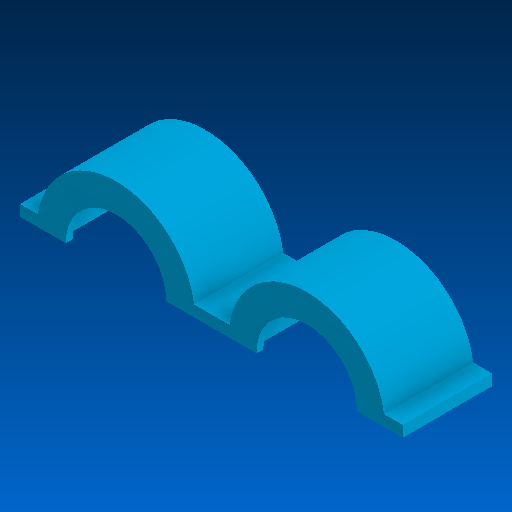
# Autodesk Inventor part: Bilge Pump Holder
Saved by Autodesk Inventor 2019 (Build 230136000, 136)
## iProperties
Created: 2018-10-23
Part Number: Bilge Pump Holder
Material: Generic
Document SubType Name: Modeling
Designer: -----
Density: 1 g/cm^3
Appearance: Sky Blue Medium
Mass: 43.4068 g
Surface Area: 140.518 cm^2
Volume: 43.4068 cm^3
Author: -----
Autodesk Inventor part; units mm, degrees
ref_plane "YZ Plane" through (0, 0, 0) normal (1, 0, 0) x (0, 1, 0)
ref_plane "XZ Plane" through (0, 0, 0) normal (0, 1, 0) x (-1, 0, 0)
ref_plane "XY Plane" through (0, 0, 0) normal (0, 0, 1) x (1, 0, 0)
sketch "Sketch1" plane through (0, 0, 0) normal (0, 1, 0) x (-1, 0, 0)
  line L0 (-0.1069, 50.4998) -> (-0.1069, 25.4998)
  arc A0 (-0.1069, -25.4998) -> (-0.1069, 25.4998) centre (0, 0) ccw
  line L1 (-0.1069, -25.4998) -> (-0.1069, -50.4998)
  line L2 (-0.1069, 50.4998) -> (4.8931, 50.4998)
  line L3 (4.8931, 50.4998) -> (4.8931, 34.6563)
  line L4 (4.8931, -34.6563) -> (4.8931, -50.4998)
  line L5 (4.8931, -50.4998) -> (-0.1069, -50.4998)
  arc A1 (4.8931, -34.6563) -> (4.8931, 34.6563) centre (0, 0) ccw
  circle A2 centre (0, 0) radius 25.5 projected
  dimension "d0" = 51
  dimension "d2" = 25
  dimension "d3" = 5
  dimension "d4" = 25
  dimension "d12" = 35
  constraints: 12 end point, 4 point on circle, 3 point on line, 2 centre point, 2 coincident, 2 vertical, 1 collinear, 1 horizontal, 1 perpendicular
  measures "d0" diameter of A0
  measures "d2" distance of L0.start L0.end
  measures "d3" distance of L0.start L2.end
  measures "d4" distance of L1.start L1.end
  measures "d12" radius of A1
extrude "Extrusion1" add sketch "Sketch1" along normal blind 34 contours L2 L3 A1 L4 L5 L1 A0 L0
sketch "Sketch2" plane through (0, 34, 0) normal (0, 1, 0) x (1, 0, 0)
  line L0 (0.1069, -50.4998) -> (0.1069, -25.4998) projected
  arc A0 (0.1069, 25.4998) -> (0.1069, -25.4998) centre (0, 0) ccw projected
  line L1 (0.1069, 25.4998) -> (0.1069, 50.4998) projected
  line L2 (0.1069, 50.4998) -> (-4.8931, 50.4998) projected
  line L3 (-4.8931, 50.4998) -> (-4.8931, 34.6563) projected
  arc A1 (-4.8931, 34.6563) -> (-4.8931, -34.6563) centre (0, 0) ccw projected
  line L4 (-4.8931, -34.6563) -> (-4.8931, -50.4998) projected
  line L5 (-4.8931, -50.4998) -> (0.1069, -50.4998) projected
  circle A2 centre (0, 0) radius 22.5
  line L6 (0.1069, -22.4997) -> (0.1069, -25.4998)
  line L7 (0.1069, 22.4997) -> (0.1069, 25.4998)
  dimension "d7" = 45
  constraints: 4 end point, 2 point on circle, 1 centre point, 1 coincident, 1 collinear, 1 point on line, 1 vertical
  measures "d7" diameter of A2
extrude "Extrusion2" add sketch "Sketch2" along normal blind 3 contours L5 L4 A1 L3 L2 L1 A0 L0 | A0 L7 A2 L6
sketch "Sketch8" plane through (0, 0, 0) normal (0, -1, 0) x (1, 0, 0)
  line L0 (0.1069, 50.4998) -> (0.1069, 25.4998) projected
  line L1 (-4.8931, 50.4998) -> (0.1069, 50.4998) projected
  line L2 (-4.8931, 34.6563) -> (-4.8931, 50.4998) projected
  arc A0 (-4.8931, 34.6563) -> (-4.8931, -34.6563) centre (0, 0) ccw projected
  line L3 (-4.8931, -50.4998) -> (-4.8931, -34.6563) projected
  line L4 (0.1069, -50.4998) -> (-4.8931, -50.4998) projected
  line L5 (0.1069, -25.4998) -> (0.1069, -50.4998) projected
  arc A1 (0.1069, 25.4998) -> (0.1069, -25.4998) centre (0, 0) ccw projected
  arc A2 (0.1069, 22.4997) -> (0.1069, -22.4997) centre (0, 0) ccw projected
  line L6 (0.1069, -22.4997) -> (0.1069, -25.4998) projected
  line L7 (0.1069, 25.4998) -> (0.1069, 22.4997) projected
extrude "Extrusion7" add sketch "Sketch8" along normal blind 3
sketch "Sketch12" plane through (0, 37, 0) normal (0, 1, 0) x (1, 0, 0)
  line L0 (0.1069, -50.4998) -> (0.1069, -22.4997) projected
  arc A0 (0.1069, 22.4997) -> (0.1069, -22.4997) centre (0, 0) ccw projected
  line L1 (0.1069, 22.4997) -> (0.1069, 50.4998) projected
  line L2 (0.1069, 50.4998) -> (-4.8931, 50.4998) projected
  line L3 (-4.8931, 50.4998) -> (-4.8931, 34.6563) projected
  arc A1 (-4.8931, 34.6563) -> (-4.8931, -34.6563) centre (0, 0) ccw projected
  line L4 (-4.8931, -34.6563) -> (-4.8931, -50.4998) projected
  line L5 (-4.8931, -50.4998) -> (0.1069, -50.4998) projected
  arc A2 (0.1069, 25.4998) -> (0.1069, -25.4998) centre (0, 0) ccw projected
  arc A3 (0.1069, 25.4998) -> (0.1069, -25.4998) centre (0, 0) ccw projected
  line L6 (0.1069, 50.4998) -> (0.1069, 85.4998)
  line L7 (0.1069, 50.4998) -> (-4.8931, 50.4998) projected
  arc A4 (-4.8931, 120.4998) -> (0.1069, 50.1444) centre (0.1069, 85.4998) ccw
  arc A5 (0.1069, 110.9998) -> (0.1069, 59.9998) centre (0.1069, 85.4998) ccw
  line L8 (0.1069, 85.4998) -> (0.1069, 120.8551)
  line L9 (0.1069, 110.9998) -> (0.1069, 135.9998)
  line L10 (0.1069, 135.9998) -> (-4.8931, 135.9998)
  line L11 (-4.8931, 135.9998) -> (-4.8931, 120.4998)
  dimension "d64" = 35
  dimension "d65" = 22.5
  dimension "d66" = 25.5
  dimension "d67" = 35
  dimension "d68" = 51
  dimension "d69" = 15.8435
  dimension "d70" = 25
  dimension "d71" = 5
  constraints: 10 end point, 5 point on circle, 4 point on line, 2 centre point, 2 coincident, 2 vertical, 1 horizontal, 1 perpendicular
  measures "d64" radius of A1
  measures "d65" radius of A0
  measures "d66" radius of A2
  measures "d67" distance of L1.end L6.end
  measures "d68" diameter of A5
  measures "d69" distance of L2.end L3.end
  measures "d70" distance of L9.start L9.end
  measures "d71" distance of L9.end L10.end
extrude "Extrusion8" add sketch "Sketch12" against normal blind 40 contours L2 A4 L11 L10 L9 L8 A5 L6
sketch "Sketch13" plane through (0, 37, 0) normal (0, 1, 0) x (1, 0, 0)
  line L0 (0.1069, -50.4998) -> (0.1069, -22.4997) projected
  arc A0 (0.1069, 22.4997) -> (0.1069, -22.4997) centre (0, 0) ccw projected
  line L1 (0.1069, 22.4997) -> (0.1069, 59.9998) projected
  arc A1 (0.1069, 110.9998) -> (0.1069, 59.9998) centre (0.1069, 85.4998) ccw projected
  line L2 (0.1069, 110.9998) -> (0.1069, 135.9998) projected
  line L3 (0.1069, 135.9998) -> (-4.8931, 135.9998) projected
  line L4 (-4.8931, 135.9998) -> (-4.8931, 120.4998) projected
  arc A2 (-4.8931, 120.4998) -> (-4.8931, 50.4998) centre (0.1069, 85.4998) ccw projected
  line L5 (-4.8931, 50.4998) -> (-4.8931, 34.6563) projected
  arc A3 (-4.8931, 34.6563) -> (-4.8931, -34.6563) centre (0, 0) ccw projected
  line L6 (-4.8931, -34.6563) -> (-4.8931, -50.4998) projected
  line L7 (-4.8931, -50.4998) -> (0.1069, -50.4998) projected
  arc A4 (0.1069, 107.9998) -> (0.1069, 62.9998) centre (0.1069, 85.4998) ccw
  arc A5 (0.1069, 110.9998) -> (0.1069, 59.9998) centre (0.1069, 85.4998) ccw projected
  line L8 (0.1069, 59.9998) -> (0.1069, 110.9998)
  dimension "d74" = 45
  constraints: 2 end point, 2 point on circle, 2 point on line, 1 centre point, 1 coincident, 1 vertical
  measures "d74" diameter of A4
extrude "Extrusion9" add sketch "Sketch13" against normal blind 3 contours A1 L8 A4
sketch "Sketch14" plane through (0, -3, 0) normal (0, -1, 0) x (1, 0, 0)
  line L0 (0.1069, -62.9998) -> (0.1069, -59.9998) projected
  arc A0 (0.1069, -59.9998) -> (0.1069, -110.9998) centre (0.1069, -85.4998) ccw projected
  line L1 (0.1069, -110.9998) -> (0.1069, -107.9998) projected
  arc A1 (0.1069, -62.9998) -> (0.1069, -107.9998) centre (0.1069, -85.4998) ccw projected
  line L2 (0.1069, -59.9998) -> (0.1069, -22.4997) projected
  arc A2 (0.1069, 22.4997) -> (0.1069, -22.4997) centre (0, 0) ccw projected
  line L3 (0.1069, 22.4997) -> (0.1069, 50.4998) projected
  line L4 (0.1069, 50.4998) -> (-4.8931, 50.4998) projected
  line L5 (-4.8931, 50.4998) -> (-4.8931, 34.6563) projected
  arc A3 (-4.8931, 34.6563) -> (-4.8931, -34.6563) centre (0, 0) ccw projected
  line L6 (-4.8931, -34.6563) -> (-4.8931, -50.4998) projected
  arc A4 (-4.8931, -50.4998) -> (-4.8931, -120.4998) centre (0.1069, -85.4998) ccw projected
  line L7 (-4.8931, -120.4998) -> (-4.8931, -135.9998) projected
  line L8 (-4.8931, -135.9998) -> (0.1069, -135.9998) projected
  line L9 (0.1069, -135.9998) -> (0.1069, -110.9998) projected
  arc A5 (0.1069, -59.9998) -> (0.1069, -110.9998) centre (0.1069, -85.4998) ccw projected
  circle A6 centre (0.1069, -85.4998) radius 22.5
  line L10 (0.1069, -62.9998) -> (0.1069, -59.9998) projected
  line L11 (0.1069, -62.9998) -> (0.1069, -59.9998)
  arc A7 (0.1069, -62.9998) -> (0.1069, -107.9998) centre (0.1069, -85.4998) ccw projected
  line L12 (0.1069, -110.9998) -> (0.1069, -107.9998) projected
  line L13 (0.1069, -107.9998) -> (0.1069, -110.9998)
  constraints: 4 end point, 2 vertical, 1 centre point, 1 coincident, 1 concentric
extrude "Extrusion10" add sketch "Sketch14" against normal blind 3 contours A1 L1 A0 L0
sketch "Sketch15" plane through (-4.8931, 37, 50.4998) normal (0, 0, 1) x (1, 0, 0)
  line L0 (5, 0) -> (5, -40) projected
  line L1 (0, 0) -> (5, 0) projected
  line L2 (0, -40) -> (0, 0) projected
  line L3 (5, -40) -> (0, -40) projected
  point P0 (4.8931, -37)
extrude "Extrusion11" cut sketch "Sketch15" against normal blind 7.5
sketch "Sketch16" plane through (0.1069, 37, -135.9998) normal (0, 0, -1) x (-1, 0, 0)
  line L0 (0, 0) -> (5, 0) projected
  line L1 (0, 0) -> (0, -40) projected
  line L2 (5, -40) -> (0, -40) projected
  line L3 (5, 0) -> (5, -40) projected
  point P0 (0.1069, -37)
extrude "Extrusion12" cut sketch "Sketch16" against normal blind 7.5
body "Solid1"
